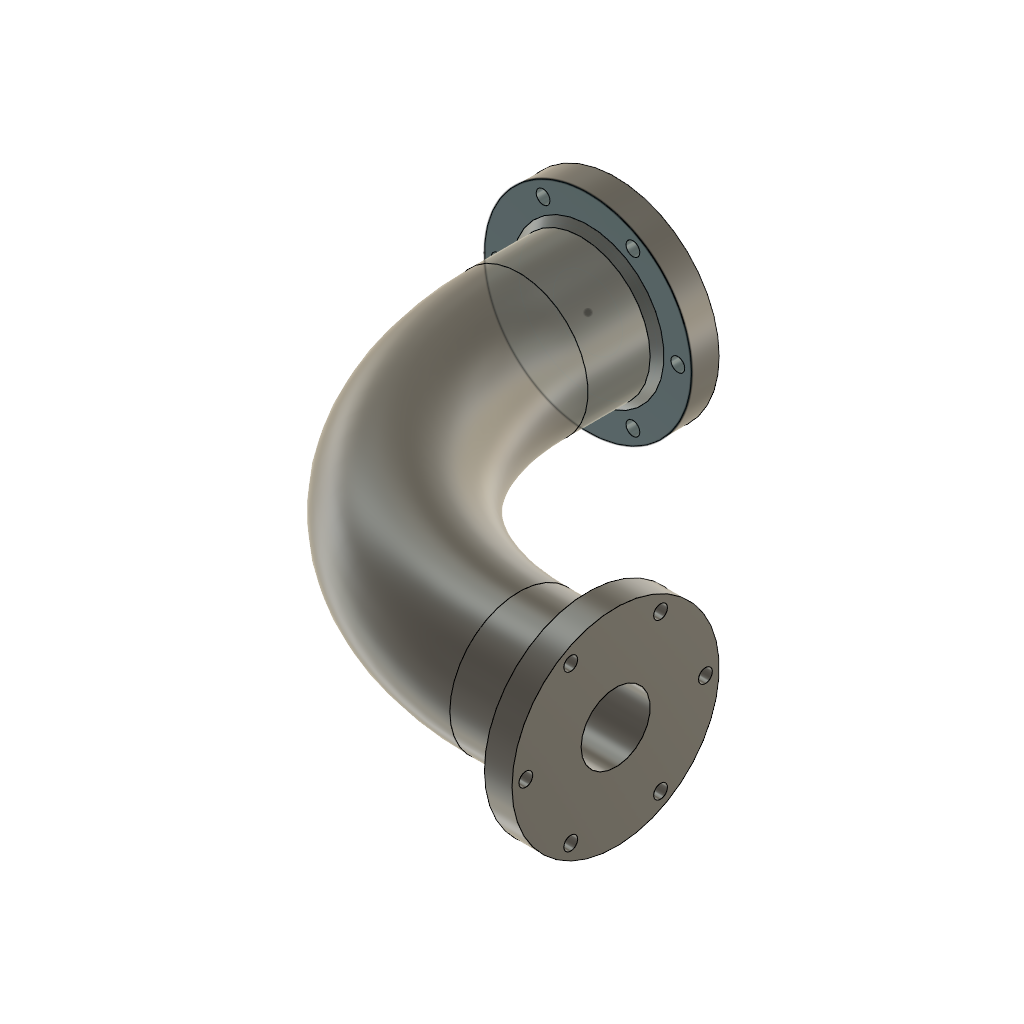
Pipe 1 (Autodesk Fusion 360 design; units mm, degrees)
part number: 2026-11-07-22-59-47-984
Autodesk Fusion 360 part; units mm, degrees
sketch "Sketch3" plane through (0, 0, 0) normal (0, 0, 1) x (1, 0, 0)
  line L0 (-242.2092, 0) -> (243.6452, 0) construction
  arc A0 (-200, 0) -> (0, -200) centre (0, 0) ccw
  line L1 (0, 32.8087) -> (0, -262.3479) construction
  line L2 (0, -200) -> (50, -200)
  line L3 (-200, 0) -> (-200, 50)
  dimension "d10" = 400
  dimension "d11" = 50
  dimension "d12" = 50
  constraint coincident A0.centre origin
  constraint horizontal L0
  constraint coincident L0 A0.start
  constraint coincident L1 A0.end
  constraint vertical L1
  constraint perpendicular L1 L2
  constraint tangent A0 L3
  constraint perpendicular L0 L3
  constraint tangent A0 L2
  measures "d10" diameter of A0
  measures "d11" distance of A0.start L3.end
  measures "d12" distance of A0.end L2.end
pipe "Pipe1" add diameter 100 wall 25 path "Sketch3" along L3 A0 L2
sketch "Sketch4" plane through (50, 0, 0) normal (1, 0, 0) x (0, 1, 0)
  circle A0 centre (-200, 0) radius 25
  circle A1 centre (-200, 0) radius 50
  circle A2 centre (-200, 0) radius 75
  line L0 (-279.8146, 0) -> (-106.5843, 0) construction
  line L1 (-200, -86.5165) -> (-200, 85.4242) construction
  circle A3 centre (-135, 0) radius 5
  circle A4 centre (-167.5, 56.2917) radius 5
  circle A5 centre (-232.5, 56.2917) radius 5
  circle A6 centre (-265, 0) radius 5
  circle A7 centre (-232.5, -56.2917) radius 5
  circle A8 centre (-167.5, -56.2917) radius 5
  dimension "d17" = 150
  dimension "d18" = 10
  dimension "d20" = 360
  dimension "d32" = 65
  constraint concentric A0 A2
  constraint horizontal L0
  constraint perpendicular L0 L1
  constraint coincident L0 A3.centre
  measures "d17" diameter of A2
  measures "d18" diameter of A3
  measures "d32" distance of A0.centre A3.centre
extrude "Extrude2" add sketch "Sketch4" along normal blind 20 contours A1 | A2
sketch "Sketch5" plane through (0, 50, 0) normal (0, 1, 0) x (-1, 0, 0)
  circle A0 centre (200, 0) radius 25
  circle A1 centre (200, 0) radius 50
  circle A2 centre (200, 0) radius 75
  dimension "d23" = 150
  constraint concentric A0 A2
  measures "d23" diameter of A2
extrude "Extrude3" add sketch "Sketch5" along normal blind 20 contours A1 | A2
sketch "Sketch6" plane through (0, 70, 0) normal (0, 1, 0) x (-1, 0, 0)
  circle A0 centre (200, 0) radius 25
  circle A1 centre (200, 0) radius 75
  circle A2 centre (265, 0) radius 5
  circle A3 centre (232.5, 56.2917) radius 5
  circle A4 centre (167.5, 56.2917) radius 5
  circle A5 centre (135, 0) radius 5
  circle A6 centre (167.5, -56.2917) radius 5
  circle A7 centre (232.5, -56.2917) radius 5
  point P0 (200, 0)
  dimension "d26" = 10
  dimension "d27" = 65
  dimension "d29" = 360
  measures "d26" diameter of A2
  measures "d27" distance of A2.centre P0
extrude "Extrude4" cut sketch "Sketch6" against normal blind 20 contours A2 | A3 | A4 | A5 | A6 | A7
chamfer "Chamfer1" distance 5 angle 45 1 edges at (50, -246.6164, -18.0808) tangent chain off
chamfer "Chamfer1" distance 5 angle 45 1 edges at (-246.6164, 50, -18.0808) tangent chain off
equation "d16 = 100 mm - 75.00 mm"
